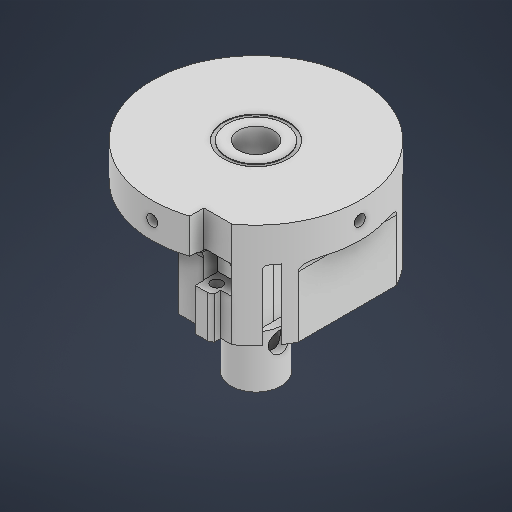
# Autodesk Inventor part: Parachute Bulkhead_V4
Saved by Autodesk Inventor 2027 (Build 310192060, 192F)
## iProperties
Created: 2026-11-01
Part Number: Parachute Bulkhead_V4
Material: Generic
Document SubType Name: Modeling
Designer: troop
Density: 1 g/cm^3
Appearance: Default
Author: troop
Autodesk Inventor part; units mm, degrees
sketch "Sketch1" plane through (0, 0, 0) normal (0, 1, 0) x (-1, 0, 0)
  circle A0 centre (0, 0) radius 37.846
  dimension "d0" = 75.692
  constraints: 1 centre point, 1 coincident
  measures "d0" diameter of A0
extrude "Extrusion1" add sketch "Sketch1" along normal blind 12.7
sketch "Sketch2" plane through (0, 0, 0) normal (0, -1, 0) x (1, 0, 0)
  circle A0 centre (0, 0) radius 6.35
  dimension "d3" = 12.7
  constraints: 1 centre point, 1 coincident
  measures "d3" diameter of A0
extrude "Extrusion2" cut sketch "Sketch2" against normal blind 19.05
sketch "Sketch3" plane through (0, 0, 0) normal (0, -1, 0) x (1, 0, 0)
  line L0 (6.35, 25.5007) -> (27.9648, 25.5007)
  line L1 (26.495, -17.9753) -> (6.35, -17.9753)
  line L2 (6.35, -17.9753) -> (6.35, 25.5007)
  circle A0 centre (0, 0) radius 37.846 projected
  circle A1 centre (0, 0) radius 6.35 projected
  line L3 (26.495, -17.9753) -> (6.35, -17.9753)
  line L4 (6.35, -21.7853) -> (6.35, -23.8497)
  line L5 (9.525, -27.0247) -> (26.495, -27.0247)
  arc A2 (6.35, -23.8497) -> (9.525, -27.0247) centre (9.525, -23.8497) ccw
  line L6 (17.1574, 25.5007) -> (6.35, 25.5007)
  circle A3 centre (25.2758, -21.9753) radius 2
  circle A4 centre (15.1892, -21.9753) radius 2
  circle A5 centre (15.1892, 29.5247) radius 2
  line L7 (30.305, -17.9753) -> (30.305, 22.67)
  line L8 (21.944, 30.8347) -> (18.01, 30.8347)
  line L9 (-25.084, 30.8347) -> (2.54, 30.8347)
  line L10 (2.54, 30.8347) -> (2.54, 5.8199)
  line L11 (2.54, -5.8199) -> (2.54, -21.7853)
  line L12 (2.54, -21.7853) -> (6.35, -21.7853)
  line L13 (26.495, -17.9753) -> (30.305, -17.9753)
  line L14 (33.3048, -17.9753) -> (33.3048, 17.9753)
  arc A6 (30.305, -22.67) -> (33.3048, -17.9753) centre (0, 0) ccw
  arc A7 (33.3048, 17.9753) -> (30.305, 22.67) centre (0, 0) ccw
  line L15 (30.9767, -17.9753) -> (30.9767, 21.7431)
  line L16 (-25.084, 30.8347) -> (11.8525, 30.8347)
  line L17 (11.8525, 30.8347) -> (11.8525, 34.0429)
  line L18 (11.8525, 34.0429) -> (16.5348, 34.0429)
  line L19 (18.01, 30.8347) -> (18.01, 33.286)
  line L20 (30.305, -17.9753) -> (30.9767, -17.9753)
  point P0 (6.35, 0)
  point P1 (6.35, -17.9753)
  point P2 (-21.944, 30.8347)
  dimension "d66" = 25.5007
  dimension "d67" = 6.35
  dimension "d68" = 6.35
  dimension "d72" = 4
  dimension "d73" = 4
  dimension "d76" = 4
  dimension "d78" = 4
  dimension "d79" = 4
  dimension "d84" = 3.81
  dimension "d85" = 21.7853
  dimension "d87" = 3.81
  dimension "d112" = 10.0866
  dimension "d113" = 17.9753
  dimension "d114" = 30.305
  dimension "d115" = 5.0292
  dimension "d116" = 33.3048
  dimension "d117" = 30.9767
  dimension "d118" = 27.0247
  dimension "d119" = 3.175
  dimension "d120" = 2.4513
  dimension "d121" = 3.2082
  dimension "d122" = 3.3367
  dimension "d142" = 30.8347
  dimension "d143" = 25.0149
  dimension "d144" = 4.024
  dimension "d145" = 40.6452
  dimension "d146" = 3.934
  constraints: 42 end point, 9 point on circle, 7 parallel, 6 centre point, 6 perpendicular, 4 horizontal, 2 tangent, 2 vertical, 1 midpoint, 1 point on line, 1 vertical alignment, 12 other
  measures "d66" distance from line of point (0, 0) L0
  measures "d67" distance from line of point (0, 0) L2
  measures "d68" distance from line of point (0, 0) L4
  measures "d72" diameter of A3
  measures "d73" distance from line of L1 A3.centre
  measures "d76" diameter of A4
  measures "d78" distance from line of L1 A4.centre
  measures "d79" diameter of A5
  measures "d84" distance between parallel lines of L2 L11
  measures "d85" distance from line of point (0, 0) L12
  measures "d87" distance between parallel lines of L2 L10
  measures "d112" distance of A3.centre A4.centre
  measures "d113" distance from line of point (0, 0) L1
  measures "d114" distance from line of point (0, 0) L7
  measures "d115" distance from line of L7 A3.centre
  measures "d116" distance from line of point (0, 0) L14
  measures "d117" distance from line of A6.centre L15
  measures "d118" distance from line of point (0, 0) L5
  measures "d119" radius of A2
  measures "d120" distance of L8.end L19.end
  measures "d121" distance of L16.end L17.end
  measures "d122" distance from line of A5.centre L17
  measures "d142" distance from line of A6.centre L16
  measures "d143" distance of L9.end L10.end
  measures "d144" distance from line of L6 A5.centre
  measures "d145" distance of L7.start L7.end
  measures "d146" distance of L8.start L8.end
ref_plane "Work Plane7" through (0, -17.4625, 0) normal (0, -1, 0) x (1, 0, 0)
ref_plane "Work Plane1" through (19.05, -17.4625, 24.892) normal (0, 0, 1) x (1, 0, 0)
sketch "Sketch6" plane through (0, 12.7, 0) normal (0, 1, 0) x (1, 0, 0)
  circle A0 centre (0, 0) radius 11.7475
  circle A1 centre (0, 0) radius 6.35 projected
  circle A2 centre (0, 0) radius 10.4775
  dimension "d36" = 23.495
  dimension "d37" = 20.955
  constraints: 2 centre point, 2 coincident
  measures "d36" diameter of A0
  measures "d37" diameter of A2
extrude "Extrusion6" cut sketch "Sketch6" against normal blind 0.889 contours A0
fillet "Fillet1" radius 0.635 2 edges at (-11.7475, 11.811, 0) (-10.4775, 11.811, 0)
sketch "Sketch7" plane through (0, 0, 0) normal (0, -1, 0) x (1, 0, 0)
  circle A0 centre (0, 0) radius 6.35
  arc A1 (6.35, 6.5619) -> (6.35, -6.5619) centre (0, 0) ccw
  line L0 (6.35, -17.9753) -> (6.35, 25.5007) projected
  point P0 (6.35, 0)
  dimension "d41" = 12.7
  dimension "d82" = 18.2626
  constraints: 2 centre point, 2 coincident, 2 point on circle, 2 point on line
  measures "d41" diameter of A0
  measures "d82" diameter of A1
ref_plane "Work Plane2" through (9.1313, 0, 0) normal (1, 0, 0) x (0, 0, -1)
ref_plane "Work Plane3" through (37.973, 0, 0) normal (1, 0, 0) x (0, 1, 0)
sketch "Sketch9" plane through (37.973, 0, 0) normal (1, 0, 0) x (0, 1, 0)
  circle A0 centre (6.35, 0) radius 1.9939
  point P0 (0, 0)
  dimension "d49" = 3.9878
  dimension "d50" = 6.35
  constraints: 1 centre point
  measures "d49" diameter of A0
  measures "d50" distance of point (0, 0) A0.centre
extrude "Extrusion9" cut sketch "Sketch9" against normal blind 5
ref_plane "Work Plane4" through (-37.973, 0, 0) normal (1, 0, 0) x (0, 1, 0)
sketch "Sketch10" plane through (-37.973, 0, 0) normal (1, 0, 0) x (0, 1, 0)
  circle A0 centre (6.35, 0) radius 1.9939 projected
  circle A1 centre (6.35, 0) radius 1.9939
  point P0 (0, 0)
  constraints: 1 centre point, 1 coincident
extrude "Extrusion10" cut sketch "Sketch10" along normal blind 5
ref_plane "Work Plane5" through (0, 0, 37.973) normal (0, 0, 1) x (1, 0, 0)
sketch "Sketch11" plane through (0, 0, 37.973) normal (0, 0, 1) x (1, 0, 0)
  circle A0 centre (0, 6.35) radius 1.9939
  point P0 (0, 0)
  dimension "d57" = 3.9878
  dimension "d58" = 6.35
  constraints: 1 centre point
  measures "d57" diameter of A0
  measures "d58" distance of point (0, 0) A0.centre
extrude "Extrusion11" cut sketch "Sketch11" against normal blind 5
ref_plane "Work Plane6" through (0, 0, -37.973) normal (0, 0, 1) x (1, 0, 0)
sketch "Sketch12" plane through (0, 0, -37.973) normal (0, 0, 1) x (1, 0, 0)
  circle A0 centre (0, 6.35) radius 1.9939 projected
  circle A1 centre (0, 6.35) radius 1.9939
  point P0 (0, 0)
  constraints: 1 centre point, 1 coincident
extrude "Extrusion12" cut sketch "Sketch12" along normal blind 5
extrude "Extrusion14" add sketch "Sketch7" along normal blind 41.275
sketch "Sketch13" plane through (0, -41.275, 0) normal (0, -1, 0) x (1, 0, 0)
  circle A0 centre (0, 0) radius 9.1313
  circle A1 centre (0, 0) radius 6.35
  dimension "d95" = 18.2626
  dimension "d96" = 12.7
  constraints: 2 centre point, 2 coincident
  measures "d95" diameter of A0
  measures "d96" diameter of A1
extrude "Extrusion15" add sketch "Sketch13" along normal blind 19.05
extrude "Extrusion19" add sketch "Sketch3" along normal blind 25.4 contours L2 A1 L10 L16 L17 L18 A0 L19 L8 L0 | L2 L1 L13 L20 L15 A0 L14 L5 A2 L4 L12 L11 A1
sketch "Sketch18" plane through (0, 0, 0) normal (0, -1, 0) x (1, 0, 0)
  line L0 (11.8525, 34.0429) -> (11.8525, 30.8347) projected
  circle A0 centre (0, 0) radius 37.846 projected
  line L1 (11.8525, 35.9421) -> (11.8525, 30.8347)
  line L2 (11.8525, 30.8347) -> (21.944, 30.8347)
  constraints: 4 end point, 2 point on circle, 1 collinear, 1 perpendicular
extrude "Extrusion21" cut sketch "Sketch18" against normal blind 25.4 contours L1 A0 L2 L0 picked at (17.5176, 31.5136)
sketch "Sketch20" plane through (6.35, -41.275, 0) normal (1, 0, 0) x (0, 0, -1)
  circle A0 centre (0, -4.935) radius 3.81
  line L0 (37.846, 41.275) -> (-37.846, 41.275) projected
  line L1 (17.9753, 15.875) -> (6.5619, 15.875) projected
  point P0 (0, 41.275)
  point P1 (27.0247, 41.275)
  point P2 (-35.9421, 41.275)
  dimension "d134" = 7.62
  dimension "d138" = 20.81
  constraints: 1 centre point
  measures "d134" diameter of A0
  measures "d138" distance from line of L1 A0.centre
extrude "Extrusion23" cut sketch "Sketch20" along normal mid plane 50.8
sketch "Sketch21" plane through (27.9648, 0, 25.5007) normal (0, 0, -1) x (-1, 0, 0)
  line L0 (0, 0) -> (21.6148, 0) projected
  line L1 (16.3193, 0) -> (6.1593, 0)
  line L2 (6.1593, 0) -> (6.1593, -10.16)
  line L3 (6.1593, -10.16) -> (16.3193, -10.16)
  line L4 (16.3193, -10.16) -> (16.3193, 0)
  line L5 (0, 0) -> (0, -25.4) projected
  point P0 (27.9648, 0)
  point P1 (6.1593, 0)
  dimension "d147" = 10.16
  dimension "d148" = 10.16
  dimension "d149" = 16.3193
  constraints: 8 end point, 2 parallel, 1 horizontal, 1 perpendicular, 1 point on line
  measures "d147" distance of L3.end L2.end
  measures "d148" distance of L3.end L1.start
  measures "d149" distance between parallel lines of L5 L4
extrude "Extrusion24" cut sketch "Sketch21" against normal blind 25.4
fillet "Fillet8" radius 3.175 9 edges at (7.2799, 0, -26.0948) (6.35, 0, -22.8175) (18.01, 0, -27.0247) (33.3048, 0, 0) (2.54, 0, -15.2781) (4.445, 0, -21.7853) (-9.1313, 0, 0) (2.54, 0, 19.8028) (7.0928, 0, 30.8347)
fillet "Fillet9" radius 1.27 5 edges at (11.6455, 0, 28.1677) (11.6455, 0, 32.4222) (8.9978, 0, 25.5007) (24.8852, 0, 25.5007) (21.8055, 0, 28.1677)
body "Solid1"
